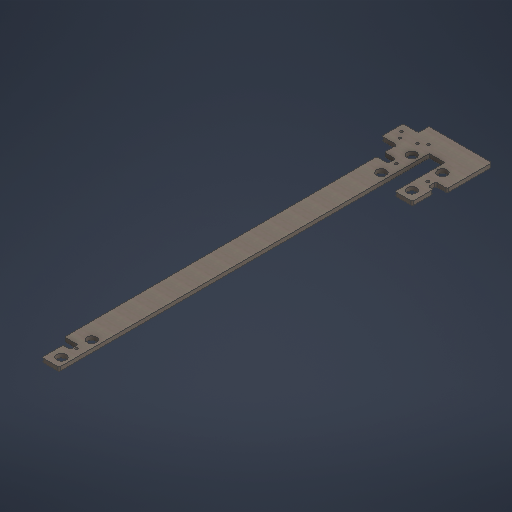
# Autodesk Inventor part: Drag Chain Support
Saved by Autodesk Inventor 2027.1 (Build 311270010, 270A)
## iProperties
Created: 2026-10-27
Part Number: Drag Chain Support
Material: Wood (Walnut)
Document SubType Name: Modeling
Designer: Ahmed
Density: 0.55 g/cm^3
Appearance: Walnut
Author: Ahmed
Autodesk Inventor part; units mm, degrees
ref_plane "YZ Plane" through (0, 0, 0) normal (1, 0, 0) x (0, 1, 0)
ref_plane "XZ Plane" through (0, 0, 0) normal (0, 1, 0) x (-1, 0, 0)
sketch "Sketch1" plane through (0, 0, 0) normal (0, 1, 0) x (-1, 0, 0)
  line L0 (10.42, 220.9998) -> (-10.42, 220.9998)
  line L1 (-15.42, 220.9998) -> (-15.42, -220.9998)
  line L2 (-0.33, -220.9998) -> (10.42, -220.9998)
  line L3 (15.42, -201.4998) -> (15.42, 201.4998)
  line L4 (15.42, 220.9998) -> (-15.42, -220.9998) construction
  line L5 (-15.42, 220.9998) -> (15.42, -220.9998) construction
  arc A0 (15.42, 215.9998) -> (10.42, 220.9998) centre (10.42, 215.9998) ccw
  arc A1 (-10.42, 220.9998) -> (-15.42, 215.9998) centre (-10.42, 215.9998) ccw
  arc A2 (-15.42, -215.9998) -> (-10.42, -220.9998) centre (-10.42, -215.9998) ccw
  circle A3 centre (-5.67, 208.4998) radius 1.65
  circle A4 centre (-5.67, -198.2498) radius 1.65
  line L6 (-2.33, -220.9998) -> (13.42, -220.9998)
  line L7 (15.42, -208.9998) -> (15.42, -203.4998)
  line L8 (13.42, -203.4998) -> (2.67, -203.4998)
  line L9 (-2.33, -205.4998) -> (-2.33, -211.4998)
  line L10 (15.42, 0) -> (-15.42, 0)
  line L11 (-2.33, 220.9998) -> (5.08, 220.9998)
  line L12 (15.42, 220.9998) -> (15.42, 203.4998)
  line L13 (13.42, 203.4998) -> (-0.33, 203.4998)
  line L14 (-2.33, 205.4998) -> (-2.33, 211.4998)
  circle A5 centre (2.0078, -191.7798) radius 1.5
  circle A6 centre (-5.67, -188.6498) radius 6.25
  circle A7 centre (-5.67, 188.6498) radius 6.25
  line L15 (-0.33, 220.9998) -> (15.42, 220.9998)
  line L16 (-15.42, 236.3485) -> (15.42, 236.3485)
  line L17 (-13.42, -220.9998) -> (5.08, -220.9998)
  line L18 (15.42, -222.9998) -> (15.42, -241.2498)
  line L19 (15.42, -241.2498) -> (-15.42, -241.2498)
  line L20 (-15.42, -241.2498) -> (-15.42, -220.9998)
  line L21 (-5.67, -188.6498) -> (-5.67, -228.3498)
  circle A8 centre (-5.67, -228.3498) radius 6.25
  arc A9 (-0.33, -203.4998) -> (-2.33, -205.4998) centre (-0.33, -205.4998) ccw
  arc A10 (-2.33, -218.9998) -> (-0.33, -220.9998) centre (-0.33, -218.9998) ccw
  arc A11 (15.42, -222.9998) -> (13.42, -220.9998) centre (13.42, -222.9998) ccw
  arc A12 (13.42, -203.4998) -> (15.42, -201.4998) centre (13.42, -201.4998) ccw
  line L22 (7.08, -215.4998) -> (7.08, -239.2498)
  line L23 (5.08, 241.2498) -> (-13.42, 241.2498)
  circle A13 centre (-5.67, 228.3498) radius 6.25
  arc A14 (-13.42, 241.2498) -> (-15.42, 239.2498) centre (-13.42, 239.2498) ccw
  arc A15 (15.42, 239.2498) -> (13.42, 241.2498) centre (13.42, 239.2498) ccw
  arc A16 (13.42, 220.9998) -> (15.42, 222.9998) centre (13.42, 222.9998) ccw
  line L24 (7.08, 222.9998) -> (7.08, 239.2498)
  line L25 (-15.42, 239.2498) -> (-15.42, 220.9998)
  arc A17 (7.08, 239.2498) -> (5.08, 241.2498) centre (5.08, 239.2498) ccw
  arc A18 (5.08, 220.9998) -> (7.08, 222.9998) centre (5.08, 222.9998) ccw
  arc A19 (-0.33, 220.9998) -> (-2.33, 218.9998) centre (-0.33, 218.9998) ccw
  arc A20 (-2.33, 205.4998) -> (-0.33, 203.4998) centre (-0.33, 205.4998) ccw
  arc A21 (15.42, 201.4998) -> (13.42, 203.4998) centre (13.42, 201.4998) ccw
  arc A22 (7.08, -222.9998) -> (5.08, -220.9998) centre (5.08, -222.9998) ccw
  arc A23 (5.08, -241.2498) -> (7.08, -239.2498) centre (5.08, -239.2498) ccw
  line L26 (7.08, 222.9998) -> (7.08, 215.4998)
  line L27 (5.08, 213.4998) -> (-0.33, 213.4998)
  arc A24 (-0.33, 213.4998) -> (-2.33, 211.4998) centre (-0.33, 211.4998) ccw
  arc A25 (5.08, 213.4998) -> (7.08, 215.4998) centre (5.08, 215.4998) ccw
  line L28 (15.42, -201.4998) -> (15.42, -210.9998)
  line L29 (2.67, -213.4998) -> (13.42, -213.4998)
  line L30 (15.42, -215.4998) -> (15.42, -222.9998)
  arc A26 (15.42, -215.4998) -> (13.42, -213.4998) centre (13.42, -215.4998) ccw
  arc A27 (-2.33, -211.4998) -> (-0.33, -213.4998) centre (-0.33, -211.4998) ccw
  arc A28 (7.08, -215.4998) -> (5.08, -213.4998) centre (5.08, -215.4998) ccw
  arc A29 (-15.42, -218.9998) -> (-13.42, -220.9998) centre (-13.42, -218.9998) ccw
  arc A30 (-15.42, -201.4998) -> (-13.42, -203.4998) centre (-13.42, -201.4998) ccw
  line L31 (15.42, -241.2498) -> (-15.42, -241.2498)
  line L32 (-35.72, -241.2498) -> (-35.72, -306.8398)
  line L33 (-35.72, -306.8398) -> (13.42, -306.8398)
  line L34 (15.42, -269.8398) -> (15.42, -241.2498)
  line L35 (-35.72, -306.8398) -> (-64.56, -306.8398)
  line L36 (-66.56, -269.8398) -> (-66.56, -215.4998)
  line L37 (-56.42, -176.2498) -> (-37.72, -176.2498)
  line L38 (-35.72, -178.2498) -> (-35.72, -306.8398)
  line L39 (-15.42, -241.2498) -> (-35.72, -241.2498)
  line L40 (-25.57, -241.2498) -> (-25.57, -238.2141)
  line L41 (-56.42, -203.4998) -> (-53.81, -203.4998)
  line L42 (-48.81, -205.4998) -> (-48.81, -211.4998)
  circle A31 centre (-45.47, -188.6498) radius 6.25
  circle A32 centre (-45.47, -228.3498) radius 6.25
  arc A33 (-66.56, -201.4998) -> (-64.56, -203.4998) centre (-64.56, -201.4998) ccw
  line L43 (-53.81, -213.4998) -> (-64.56, -213.4998)
  arc A34 (-50.81, -213.4998) -> (-48.81, -211.4998) centre (-50.81, -211.4998) ccw
  arc A35 (-48.81, -205.4998) -> (-50.81, -203.4998) centre (-50.81, -205.4998) ccw
  arc A36 (-64.56, -213.4998) -> (-66.56, -215.4998) centre (-64.56, -215.4998) ccw
  line L44 (-66.56, -178.2498) -> (-66.56, -201.4998)
  arc A37 (-64.56, -176.2498) -> (-66.56, -178.2498) centre (-64.56, -178.2498) ccw
  arc A38 (-35.72, -178.2498) -> (-37.72, -176.2498) centre (-37.72, -178.2498) ccw
  arc A39 (-66.56, -304.8398) -> (-64.56, -306.8398) centre (-64.56, -304.8398) ccw
  arc A40 (13.42, -306.8398) -> (15.42, -304.8398) centre (13.42, -304.8398) ccw
  circle A41 centre (-45.96, -208.7498) radius 2
  line L45 (-51.81, -205.4998) -> (-51.81, -211.4998)
  arc A42 (-51.81, -205.4998) -> (-53.81, -203.4998) centre (-53.81, -205.4998) ccw
  arc A43 (-53.81, -213.4998) -> (-51.81, -211.4998) centre (-53.81, -211.4998) ccw
  line L46 (0.67, -205.4998) -> (0.67, -211.4998)
  arc A44 (2.67, -203.4998) -> (0.67, -205.4998) centre (2.67, -205.4998) ccw
  arc A45 (0.67, -211.4998) -> (2.67, -213.4998) centre (2.67, -211.4998) ccw
  line L47 (-64.56, -271.8398) -> (13.42, -271.8398)
  arc A46 (-66.56, -269.8398) -> (-64.56, -271.8398) centre (-64.56, -269.8398) ccw
  arc A47 (13.42, -271.8398) -> (15.42, -269.8398) centre (13.42, -269.8398) ccw
  circle A48 centre (-5.18, -208.7498) radius 2
  line L48 (-58.42, -178.2498) -> (-58.42, -201.4998)
  arc A49 (-56.42, -176.2498) -> (-58.42, -178.2498) centre (-56.42, -178.2498) ccw
  arc A50 (-58.42, -201.4998) -> (-56.42, -203.4998) centre (-56.42, -201.4998) ccw
  point P0 (0, 0)
  point P1 (-2.33, -203.4998)
  point P2 (-2.33, 203.4998)
  point P3 (15.42, -203.4998)
  point P4 (15.42, 317.2502)
  point P5 (-2.33, 334.7502)
  point P6 (15.42, -220.9998)
  point P7 (10.42, 277.875)
  point P8 (15.42, 215.9998)
  point P9 (15.42, 241.2498)
  point P10 (-15.42, 241.2498)
  point P11 (7.08, 220.9998)
  point P12 (7.08, 241.2498)
  point P13 (-0.33, 220.9998)
  point P14 (-0.33, -220.9998)
  point P15 (5.08, 220.9998)
  point P16 (7.08, 220.9998)
  point P17 (15.42, -213.4998)
  point P18 (7.08, -220.9998)
  point P19 (5.08, -220.9998)
  point P20 (7.08, -220.9998)
  point P21 (-15.42, -203.4998)
  point P22 (7.08, -241.2498)
  point P23 (-15.42, -231.1248)
  point P24 (-66.56, -176.2498)
  point P25 (-66.56, -306.8398)
  point P26 (-48.81, -205.4998)
  point P27 (-37.72, -203.4998)
  point P28 (-64.56, -213.4998)
  point P29 (-35.72, -271.8398)
  point P30 (-58.42, -189.8748)
  dimension "d0" = 30.84
  dimension "d1" = 441.9996
  dimension "d3" = 3.3
  dimension "d4" = 12.5
  dimension "d5" = 3.3
  dimension "d6" = 22.75
  dimension "d9" = 9.75
  dimension "d10" = 9.75
  dimension "d11" = 17.75
  dimension "d12" = 17.5
  dimension "d15" = 3
  dimension "d17" = 11.72
  dimension "d18" = 13.4122
  dimension "d19" = 21.09
  dimension "d20" = 32.35
  dimension "d21" = 12.5
  dimension "d25" = 30.84
  dimension "d27" = 5
  dimension "d28" = 439.8483
  dimension "d29" = 0
  dimension "d30" = 0
  dimension "d31" = 520.75
  dimension "d32" = 0
  dimension "d33" = 0
  dimension "d34" = 5
  dimension "d35" = 538.25
  dimension "d36" = 17.75
  dimension "d37" = 538.25
  dimension "d38" = 20.25
  dimension "d41" = 30.84
  dimension "d42" = 39.7
  dimension "d43" = 12.5
  dimension "d45" = 2
  dimension "d46" = 8.34
  dimension "d47" = 2
  dimension "d48" = 2
  dimension "d49" = 7.5
  dimension "d50" = 2
  dimension "d53" = 7.5
  dimension "d54" = 9.5
  dimension "d55" = 2
  dimension "d56" = 2
  dimension "d57" = 2
  dimension "d58" = 2
  dimension "d59" = 65.59
  dimension "d61" = 20.3
  dimension "d62" = 30.84
  dimension "d63" = 65
  dimension "d64" = 3.0357
  dimension "d65" = 2
  dimension "d66" = 2
  dimension "d67" = 2
  dimension "d68" = 2
  dimension "d69" = 4
  dimension "d70" = 10.24
  dimension "d71" = 32.5
  dimension "d102" = 3
  dimension "d103" = 2
  dimension "d104" = 3
  dimension "d105" = 2
  dimension "d124" = 35
  dimension "d125" = 2
  dimension "d126" = 8.14
  dimension "d127" = 2
  constraints: 96 end point, 81 point on circle, 67 tangent, 62 point on line, 51 centre point, 25 symmetric about line, 18 equal radius, 13 perpendicular, 10 parallel, 9 horizontal, 6 midpoint, 3 vertical, 1 coincident, 1 collinear, 22 other
  measures "d0" distance of L4.end L5.end
  measures "d1" distance of L4.end L5.start
  measures "d3" diameter of A3
  measures "d4" distance from line of A3.centre L0
  measures "d5" diameter of A4
  measures "d6" distance from line of L2 A4.centre
  measures "d11" distance of point (-2.33, -203.5) L7.end
  measures "d12" distance of L7.end point (15.42, -221)
  measures "d15" diameter of A5
  measures "d17" distance from line of L8 A5.centre
  measures "d18" distance from line of L3 A5.centre
  measures "d19" distance from line of L3 L21.start
  measures "d20" distance from line of L2 L21.start
  measures "d21" diameter of A6
  measures "d25" distance of L10.start L10.end
  measures "d27" radius of A0
  measures "d28" distance between parallel lines of L16 L8
  measures "d29" distance from line of L15.end L12
  measures "d30" distance from line of point (15.42, 317.25) L12
  measures "d31" distance from line of point (15.42, 317.25) L8
  measures "d32" distance from line of point (15.42, -203.5) L12
  measures "d33" distance from line of point (15.42, -203.5) L8
  measures "d36" distance from line of point (-2.33, 334.75) L12
  measures "d37" distance from line of point (-2.33, 334.75) L8
  measures "d38" distance of L18.end point (15.42, -221)
  measures "d41" distance of L19.end L18.end
  measures "d42" distance of L21.start L21.end
  measures "d43" diameter of A8
  measures "d45" radius of A9
  measures "d46" distance between parallel lines of L18 L22
  measures "d47" radius of A17
  measures "d48" radius of A22
  measures "d49" distance from line of point (7.08, 221) L27
  measures "d50" radius of A24
  measures "d53" distance between parallel lines of L2 L29
  measures "d54" distance of point (15.42, -213.5) L30.end
  measures "d55" radius of A26
  measures "d56" radius of A28
  measures "d57" radius of A29
  measures "d58" radius of A30
  measures "d59" distance of L32.end L32.start
  measures "d61" distance from line of point (-15.42, -231.125) L32
  measures "d62" distance of L32.end point (-66.56, -306.84)
  measures "d63" distance between parallel lines of L31 L37
  measures "d64" distance of L40.start L40.end
  measures "d65" radius of A35
  measures "d66" radius of A37
  measures "d67" radius of A39
  measures "d68" radius of A40
  measures "d69" diameter of A41
  measures "d70" distance from line of L38 A41.centre
  measures "d71" distance from line of L37 A41.centre
  measures "d102" distance between parallel lines of L42 L45
  measures "d103" radius of A42
  measures "d104" distance between parallel lines of L9 L46
  measures "d105" radius of A44
  measures "d124" distance between parallel lines of L33 L47
  measures "d125" radius of A46
  measures "d126" distance from line of L44 point (-58.42, -189.875)
  measures "d127" radius of A49
extrude "Extrusion1" add sketch "Sketch1" along normal blind 5 contours L0 L26 A25 L27 A24 L14 A20 L13 A21 L3 L10 L1 A1 | A18 L26 L0 | L0 A1 L1 L25 L16 L24 A18 | L16 L25 A14 L23 A17 L24 | A4 L21 | L21 A4 | L10 L3 A12 L8 A44 L46 A45 L29 A28 L22 L2 L6 L17 A2 L1 | A2 L17 A29 L1 | A29 L17 L6 L2 A22 L22 A23 L19 L20 L1 | L19 L34 A47 L47 L32 L39 | A23 L22 L2 L6 A11 L18 L19 | L32 L47 A46 L36 A36 L43 A43 L45 A42 L41 A50 L48 A49 L37 A38 L38 | L2 L22 A22 | A11 L6 L2 L22 A28 L29 A26 L30 | A5
sketch "Sketch2" plane through (0, 0, 0) normal (0, -1, 0) x (1, 0, 0)
  line L0 (66.56, -215.4998) -> (66.56, -269.8398) projected
  line L1 (14.42, -260.3502) -> (-14.42, -260.3502)
  line L2 (-14.42, -260.3502) -> (-14.42, -229.5102)
  line L3 (-14.42, -229.5102) -> (14.42, -229.5102)
  line L4 (14.42, -229.5102) -> (14.42, -260.3502)
  line L5 (14.42, -257.3502) -> (-14.42, -257.3502)
  line L6 (-5.25, -244.8498) -> (-2.25, -244.8498) construction
  line L7 (-5.25, -246.3498) -> (-2.25, -246.3498)
  line L8 (-2.25, -243.3498) -> (-5.25, -243.3498)
  arc A0 (-5.25, -243.3498) -> (-5.25, -246.3498) centre (-5.25, -244.8498) ccw
  arc A1 (-2.25, -246.3498) -> (-2.25, -243.3498) centre (-2.25, -244.8498) ccw
  line L9 (3.25, -250.8498) -> (6.25, -250.8498) construction
  line L10 (6.25, -249.3498) -> (3.25, -249.3498)
  arc A2 (6.25, -252.3498) -> (6.25, -249.3498) centre (6.25, -250.8498) ccw
  arc A3 (3.25, -249.3498) -> (3.25, -252.3498) centre (3.25, -250.8498) ccw
  line L11 (3.25, -252.3498) -> (6.25, -252.3498)
  circle A4 centre (4.75, -250.8498) radius 1.75
  circle A5 centre (-3.75, -244.8498) radius 1.75
  circle A6 centre (5.67, -228.3498) radius 6.25 projected
  point P0 (0, 0)
  point P1 (-3.75, -246.3498)
  point P2 (4.75, -252.3498)
  dimension "d76" = 30.84
  dimension "d77" = 28.84
  dimension "d78" = 3
  dimension "d79" = 3
  dimension "d80" = 3
  dimension "d81" = 3
  dimension "d82" = 3
  dimension "d83" = 3.5
  dimension "d84" = 3.5
  dimension "d85" = 6
  dimension "d86" = 8.5
  dimension "d87" = 5.0004
  dimension "d89" = 9.67
  dimension "d106" = 15
  constraints: 26 end point, 8 point on circle, 8 tangent, 6 centre point, 4 midpoint, 4 parallel, 3 horizontal, 2 coincident, 2 perpendicular, 2 point on line
  measures "d76" distance of L1.end L2.end
  measures "d77" distance between parallel lines of L2 L4
  measures "d78" distance between parallel lines of L1 L5
  measures "d79" diameter of A1
  measures "d80" distance of L6.start L6.end
  measures "d81" diameter of A2
  measures "d82" distance of L9.start L9.end
  measures "d83" diameter of A4
  measures "d84" diameter of A5
  measures "d85" vertical distance of point (-3.75, -246.35) point (4.75, -252.35)
  measures "d86" horizontal distance of point (-3.75, -244.85) point (4.75, -250.85)
  measures "d87" distance between parallel lines of L5 L11
  measures "d89" distance from line of L4 point (4.75, -250.85)
  measures "d106" distance from line of A6.centre L8
extrude "Extrusion2" cut sketch "Sketch2" against normal through all contours A5 L8 L7 | L7 A5 | A5 L8 | A4 L11 L10 | L10 A4 | A4 L11
sketch "Sketch3" plane through (0, 5, 0) normal (0, 1, 0) x (1, 0, 0)
  line L0 (66.56, 215.4998) -> (66.56, 269.8398) projected
  line L1 (68.56, 257.8497) -> (84.56, 257.8497)
  line L2 (86.56, 255.8497) -> (86.56, 232.0097)
  line L3 (84.56, 230.0097) -> (68.56, 230.0097)
  line L4 (66.56, 230.0097) -> (66.56, 257.8497)
  arc A0 (84.56, 230.0097) -> (86.56, 232.0097) centre (84.56, 232.0097) ccw
  arc A1 (86.56, 255.8497) -> (84.56, 257.8497) centre (84.56, 255.8497) ccw
  line L5 (66.56, 228.0097) -> (66.56, 224.0468)
  line L6 (66.56, 259.8497) -> (66.56, 262.1547)
  arc A2 (68.56, 230.0097) -> (66.56, 228.0097) centre (68.56, 228.0097) ccw
  arc A3 (66.56, 259.8497) -> (68.56, 257.8497) centre (68.56, 259.8497) ccw
  line L7 (72.5019, 238.1797) -> (72.5019, 241.1797) construction
  line L8 (74.0019, 238.1797) -> (74.0019, 241.1797)
  line L9 (71.0019, 241.1797) -> (71.0019, 238.1797)
  arc A4 (71.0019, 238.1797) -> (74.0019, 238.1797) centre (72.5019, 238.1797) ccw
  arc A5 (74.0019, 241.1797) -> (71.0019, 241.1797) centre (72.5019, 241.1797) ccw
  line L10 (78.5019, 246.6797) -> (78.5019, 249.6797) construction
  line L11 (77.0019, 249.6797) -> (77.0019, 246.6797)
  arc A6 (80.0019, 249.6797) -> (77.0019, 249.6797) centre (78.5019, 249.6797) ccw
  arc A7 (77.0019, 246.6797) -> (80.0019, 246.6797) centre (78.5019, 246.6797) ccw
  line L12 (80.0019, 246.6797) -> (80.0019, 249.6797)
  circle A8 centre (78.5019, 248.1797) radius 1.75
  circle A9 centre (72.5019, 239.6797) radius 1.75
  line L13 (15.42, 241.2498) -> (35.72, 241.2498) projected
  line L14 (25.57, 241.2498) -> (25.57, 255.8497)
  line L15 (-15.42, 215.4998) -> (-15.42, 304.8398)
  line L16 (-17.42, 257.8497) -> (-33.42, 257.8497)
  line L17 (-35.42, 255.8497) -> (-35.42, 232.0097)
  line L18 (-33.42, 230.0097) -> (-17.42, 230.0097)
  line L19 (-15.42, 230.0097) -> (-15.42, 257.8497)
  arc A10 (-35.42, 232.0097) -> (-33.42, 230.0097) centre (-33.42, 232.0097) ccw
  arc A11 (-33.42, 257.8497) -> (-35.42, 255.8497) centre (-33.42, 255.8497) ccw
  arc A12 (-15.42, 228.0097) -> (-17.42, 230.0097) centre (-17.42, 228.0097) ccw
  arc A13 (-17.42, 257.8497) -> (-15.42, 259.8497) centre (-17.42, 259.8497) ccw
  arc A14 (-28.8619, 246.6797) -> (-25.8619, 246.6797) centre (-27.3619, 246.6797) ccw
  line L20 (-25.8619, 249.6797) -> (-25.8619, 246.6797)
  line L21 (-27.3619, 246.6797) -> (-27.3619, 249.6797) construction
  line L22 (-28.8619, 246.6797) -> (-28.8619, 249.6797)
  circle A15 centre (-27.3619, 248.1797) radius 1.75
  arc A16 (-25.8619, 249.6797) -> (-28.8619, 249.6797) centre (-27.3619, 249.6797) ccw
  arc A17 (-19.8619, 241.1797) -> (-22.8619, 241.1797) centre (-21.3619, 241.1797) ccw
  line L23 (-22.8619, 238.1797) -> (-22.8619, 241.1797)
  line L24 (-21.3619, 238.1797) -> (-21.3619, 241.1797) construction
  circle A18 centre (-21.3619, 239.6797) radius 1.75
  arc A19 (-22.8619, 238.1797) -> (-19.8619, 238.1797) centre (-21.3619, 238.1797) ccw
  point P0 (0, 0)
  point P1 (86.56, 230.0097)
  point P2 (86.56, 257.8497)
  point P3 (74.0019, 239.6797)
  point P4 (80.0019, 248.1797)
  point P5 (-35.42, 230.0097)
  point P6 (-35.42, 257.8497)
  point P7 (-28.8619, 248.1797)
  point P8 (-22.8619, 239.6797)
  point P9 (74.0019, 238.7783)
  point P10 (71.0019, 238.7783)
  point P11 (71.0019, 240.5811)
  point P12 (74.0019, 240.5811)
  point P13 (77.0019, 249.0811)
  point P14 (80.0019, 249.0811)
  point P15 (80.0019, 247.2783)
  point P16 (77.0019, 247.2783)
  dimension "d107" = 20
  dimension "d108" = 27.84
  dimension "d110" = 2
  dimension "d111" = 2
  dimension "d112" = 3
  dimension "d113" = 3
  dimension "d114" = 3
  dimension "d115" = 3
  dimension "d116" = 3.5
  dimension "d117" = 3.5
  dimension "d118" = -8.5
  dimension "d119" = 6
  dimension "d120" = 5.9419
  dimension "d121" = 9.67
  constraints: 54 end point, 35 symmetric about line, 32 point on circle, 20 centre point, 18 point on line, 16 tangent, 5 midpoint, 4 coincident, 4 parallel, 2 equal radius, 1 horizontal, 1 perpendicular, 1 vertical, 10 other
  measures "d107" distance of point (86.56, 230.01) L4.start
  measures "d108" distance of point (86.56, 257.85) point (86.56, 230.01)
  measures "d110" radius of A0
  measures "d111" radius of A2
  measures "d112" diameter of A5
  measures "d113" distance of L7.start L7.end
  measures "d114" diameter of A6
  measures "d115" distance of L10.start L10.end
  measures "d116" diameter of A8
  measures "d117" diameter of A9
  measures "d118" vertical distance of point (74.002, 239.68) point (80.002, 248.18)
  measures "d119" horizontal distance of point (72.502, 239.68) point (78.502, 248.18)
  measures "d120" distance from line of L0 point (72.502, 239.68)
  measures "d121" distance from line of L3 point (72.502, 239.68)
extrude "Extrusion3" add sketch "Sketch3" against normal blind 5 contours A12 L18 A10 L17 A11 L16 A13 L15 | L22 A15 L20 A14 | L22 A16 L20 A15
ref_plane "Work Plane2" through (25.57, 0, 239.2498) normal (1, 0, 0) x (0, 0, -1)
equation "\"d5\" = d3"
equation "\"d9\" = d10"
equation "\"d43\" = d21"
equation "\"d62\" = d0"
body "Solid1"
